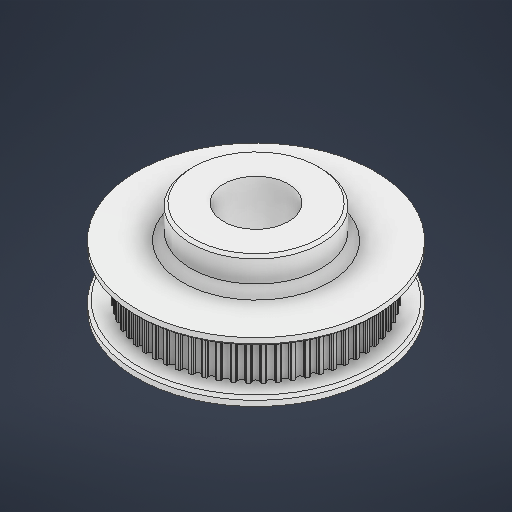
# Autodesk Inventor part: pulleyGT3_12mm
Saved by Autodesk Inventor 2027.1 (Build 311270010, 270A)
## iProperties
Created: 2026-10-09
Part Number: pulleyGT3_12mm
Material: ABS Plastic
Document SubType Name: Modeling
Designer: lucao
Density: 1.06 g/cm^3
Appearance: Smooth - White
Mass: 14.8145 g
Surface Area: 63.8885 cm^2
Volume: 13.9759 cm^3
Author: lucao
Autodesk Inventor part; units mm, degrees
ref_plane "YZ Plane" through (0, 0, 0) normal (1, 0, 0) x (0, 1, 0)
ref_plane "XZ Plane" through (0, 0, 0) normal (0, 1, 0) x (-1, 0, 0)
ref_plane "XY Plane" through (0, 0, 0) normal (0, 0, 1) x (1, 0, 0)
sketch "Sketch1" plane through (0, 0, 0) normal (0, 1, 0) x (-1, 0, 0)
  circle A0 centre (0, 0) radius 19.099
  dimension "d0" = 38.198
  constraints: 1 centre point, 1 coincident
  measures "d0" diameter of A0
extrude "Extrusion1" add sketch "Sketch1" along normal blind 8
sketch "Sketch2" plane through (0, 8, 0) normal (0, 1, 0) x (1, 0, 0)
  circle A0 centre (0, 0) radius 19.099 projected
  line L0 (0, 0) -> (-19.099, 0) construction
  arc A1 (-18.8433, 0.2558) -> (-18.845, 0) centre (0, 0) ccw
  arc A2 (-18.7068, 0.4032) -> (-18.8433, 0.2558) centre (-18.6933, 0.2538) ccw
  arc A3 (-18.7068, 0.4032) -> (-18.4073, 0.4782) centre (-18.7972, 1.3991) ccw
  arc A4 (-18.4073, 0.4782) -> (-18.0695, 0.9599) centre (-18.6237, 0.9893) ccw
  line L1 (0, 0) -> (-18.6237, 0.9893) construction
  arc A5 (-18.8185, 0.9996) -> (-18.8433, 0.2558) centre (0, 0) ccw construction
  arc A6 (-18.5981, 3.0405) -> (-18.8185, 0.9996) centre (0, 0) ccw construction
  arc A7 (-18.7389, 1.9965) -> (-18.7643, 1.7419) centre (0, 0) ccw
  arc A8 (-18.7643, 1.7419) -> (-18.6443, 1.5809) centre (-18.615, 1.728) ccw
  arc A9 (-18.3544, 1.4746) -> (-18.6443, 1.5809) centre (-18.8397, 0.6002) ccw
  arc A10 (-18.0695, 0.9599) -> (-18.3544, 1.4746) centre (-18.6237, 0.9893) ccw
  arc A11 (-18.7668, -1.7152) -> (-18.7418, -1.9698) centre (0, 0) ccw
  arc A12 (-18.6465, -1.5544) -> (-18.3565, -1.4485) centre (-18.8405, -0.5734) ccw
  arc A13 (-18.3565, -1.4485) -> (-18.0709, -0.9342) centre (-18.6251, -0.9628) ccw
  arc A14 (-18.0709, -0.9342) -> (-18.408, -0.4521) centre (-18.6251, -0.9628) ccw
  arc A15 (-18.8436, -0.229) -> (-18.7074, -0.3766) centre (-18.6936, -0.2272) ccw
  arc A16 (-18.408, -0.4521) -> (-18.7074, -0.3766) centre (-18.7992, -1.3724) ccw
  arc A17 (-18.845, 0.0268) -> (-18.8436, -0.229) centre (0, 0) ccw
  arc A18 (-18.6465, -1.5544) -> (-18.7668, -1.7152) centre (-18.6174, -1.7016) ccw
  arc A19 (-18.4847, -3.6675) -> (-18.4332, -3.9181) centre (0, 0) ccw
  arc A20 (-18.3819, -3.495) -> (-18.1045, -3.3593) centre (-18.6774, -2.5397) ccw
  arc A21 (-18.1045, -3.3593) -> (-17.8742, -2.818) centre (-18.4225, -2.9044) ccw
  arc A22 (-17.8742, -2.818) -> (-18.2599, -2.3737) centre (-18.4225, -2.9044) ccw
  arc A23 (-18.7164, -2.1975) -> (-18.5655, -2.33) centre (-18.5675, -2.18) ccw
  arc A24 (-18.2599, -2.3737) -> (-18.5655, -2.33) centre (-18.5528, -3.3299) ccw
  arc A25 (-18.7445, -1.9432) -> (-18.7164, -2.1975) centre (0, 0) ccw
  arc A26 (-18.3819, -3.495) -> (-18.4847, -3.6675) centre (-18.3376, -3.6383) ccw
  arc A27 (-18.0001, -5.5796) -> (-17.9227, -5.8234) centre (0, 0) ccw
  arc A28 (-17.9159, -5.3973) -> (-17.6542, -5.2334) centre (-18.3096, -4.4781) ccw
  arc A29 (-17.6542, -5.2334) -> (-17.4818, -4.6709) centre (-18.0179, -4.8142) ccw
  arc A30 (-17.4818, -4.6709) -> (-17.9118, -4.2694) centre (-18.0179, -4.8142) ccw
  arc A31 (-18.3842, -4.1418) -> (-18.2203, -4.2578) centre (-18.2379, -4.1089) ccw
  arc A32 (-17.9118, -4.2694) -> (-18.2203, -4.2578) centre (-18.1031, -5.2509) ccw
  arc A33 (-18.4387, -3.8919) -> (-18.3842, -4.1418) centre (0, 0) ccw
  arc A34 (-17.9159, -5.3973) -> (-18.0001, -5.5796) centre (-17.8568, -5.5352) ccw
  arc A35 (-17.3182, -7.4305) -> (-17.2158, -7.665) centre (0, 0) ccw
  arc A36 (-17.2535, -7.2404) -> (-17.0105, -7.0501) centre (-17.7412, -6.3674) ccw
  arc A37 (-17.0105, -7.0501) -> (-16.8977, -6.4727) centre (-17.416, -6.6712) ccw
  arc A38 (-16.8977, -6.4727) -> (-17.3674, -6.1183) centre (-17.416, -6.6712) ccw
  arc A39 (-17.8506, -6.0408) -> (-17.6754, -6.1391) centre (-17.7085, -5.9927) ccw
  arc A40 (-17.3674, -6.1183) -> (-17.6754, -6.1391) centre (-17.455, -7.1145) ccw
  arc A41 (-17.9309, -5.7979) -> (-17.8506, -6.0408) centre (0, 0) ccw
  arc A42 (-17.2535, -7.2404) -> (-17.3182, -7.4305) centre (-17.1804, -7.3714) ccw
  arc A43 (-16.4467, -9.2001) -> (-16.3202, -9.4225) centre (0, 0) ccw
  arc A44 (-16.4022, -9.0043) -> (-16.1803, -8.7895) centre (-16.9784, -8.187) ccw
  arc A45 (-16.1803, -8.7895) -> (-16.1286, -8.2035) centre (-16.6233, -8.4551) ccw
  arc A46 (-16.1286, -8.2035) -> (-16.6327, -7.9002) centre (-16.6233, -8.4551) ccw
  arc A47 (-17.1213, -7.8736) -> (-16.9369, -7.953) centre (-16.9851, -7.811) ccw
  arc A48 (-16.6327, -7.9002) -> (-16.9369, -7.953) centre (-16.6158, -8.9) ccw
  arc A49 (-17.2266, -7.6405) -> (-17.1213, -7.8736) centre (0, 0) ccw
  arc A50 (-16.4022, -9.0043) -> (-16.4467, -9.2001) centre (-16.3158, -9.1268) ccw
  arc A51 (-15.3949, -10.8688) -> (-15.2459, -11.0768) centre (0, 0) ccw
  arc A52 (-15.3711, -10.6694) -> (-15.173, -10.4327) centre (-16.0297, -9.9169) ccw
  arc A53 (-15.173, -10.4327) -> (-15.1827, -9.8445) centre (-15.6484, -10.1464) ccw
  arc A54 (-15.1827, -9.8445) -> (-15.7158, -9.5955) centre (-15.6484, -10.1464) ccw
  arc A55 (-16.2045, -9.6202) -> (-16.0128, -9.6798) centre (-16.0755, -9.5436) ccw
  arc A56 (-15.7158, -9.5955) -> (-16.0128, -9.6798) centre (-15.5944, -10.5881) ccw
  arc A57 (-16.3336, -9.3993) -> (-16.2045, -9.6202) centre (0, 0) ccw
  arc A58 (-15.3711, -10.6694) -> (-15.3949, -10.8688) centre (-15.2724, -10.7823) ccw
  arc A59 (-14.1745, -12.4185) -> (-14.0046, -12.6098) centre (0, 0) ccw
  arc A60 (-14.1717, -12.2177) -> (-13.9993, -11.9615) centre (-14.9052, -11.5381) ccw
  arc A61 (-13.9993, -11.9615) -> (-14.0705, -11.3776) centre (-14.5021, -11.7265) ccw
  arc A62 (-14.0705, -11.3776) -> (-14.6267, -11.1857) centre (-14.5021, -11.7265) ccw
  arc A63 (-15.1102, -11.2613) -> (-14.9132, -11.3006) centre (-14.9899, -11.1717) ccw
  arc A64 (-14.6267, -11.1857) -> (-14.9132, -11.3006) centre (-14.4022, -12.1602) ccw
  arc A65 (-15.2617, -11.0551) -> (-15.1102, -11.2613) centre (0, 0) ccw
  arc A66 (-14.1717, -12.2177) -> (-14.1745, -12.4185) centre (-14.0616, -12.3196) ccw
  arc A67 (-12.7987, -13.8321) -> (-12.6098, -14.0046) centre (0, 0) ccw
  arc A68 (-12.8169, -13.6321) -> (-12.6723, -13.3593) centre (-13.6175, -13.0329) ccw
  arc A69 (-12.6723, -13.3593) -> (-12.8042, -12.786) centre (-13.1969, -13.1782) ccw
  arc A70 (-12.8042, -12.786) -> (-13.3773, -12.6533) centre (-13.1969, -13.1782) ccw
  arc A71 (-13.8503, -12.779) -> (-13.6503, -12.7975) centre (-13.74, -12.6773) ccw
  arc A72 (-13.3773, -12.6533) -> (-13.6503, -12.7975) centre (-13.0523, -13.599) ccw
  arc A73 (-14.0225, -12.5898) -> (-13.8503, -12.779) centre (0, 0) ccw
  arc A74 (-12.8169, -13.6321) -> (-12.7987, -13.8321) centre (-12.6969, -13.722) ccw
  arc A75 (-11.2828, -15.0941) -> (-11.0768, -15.2459) centre (0, 0) ccw
  arc A76 (-11.3218, -14.8972) -> (-11.2065, -14.6108) centre (-12.1806, -14.3849) ccw
  arc A77 (-11.2065, -14.6108) -> (-11.3975, -14.0544) centre (-11.7471, -14.4854) ccw
  arc A78 (-11.3975, -14.0544) -> (-11.9814, -13.9823) centre (-11.7471, -14.4854) ccw
  arc A79 (-12.4386, -14.1568) -> (-12.2378, -14.1543) centre (-12.3396, -14.0441) ccw
  arc A80 (-11.9814, -13.9823) -> (-12.2378, -14.1543) centre (-11.5593, -14.8888) ccw
  arc A81 (-12.6297, -13.9866) -> (-12.4386, -14.1568) centre (0, 0) ccw
  arc A82 (-11.3218, -14.8972) -> (-11.2828, -15.0941) centre (-11.193, -14.974) ccw
  arc A83 (-9.6432, -16.1908) -> (-9.4225, -16.3202) centre (0, 0) ccw
  arc A84 (-9.7026, -15.999) -> (-9.6178, -15.7021) centre (-10.6103, -15.5794) ccw
  arc A85 (-9.6178, -15.7021) -> (-9.866, -15.1687) centre (-10.1686, -15.634) ccw
  arc A86 (-9.866, -15.1687) -> (-10.4542, -15.1581) centre (-10.1686, -15.634) ccw
  arc A87 (-10.8907, -15.3794) -> (-10.6913, -15.356) centre (-10.804, -15.257) ccw
  arc A88 (-10.4542, -15.1581) -> (-10.6913, -15.356) centre (-9.9396, -16.0155) ccw
  arc A89 (-11.0985, -15.2302) -> (-10.8907, -15.3794) centre (0, 0) ccw
  arc A90 (-9.7026, -15.999) -> (-9.6432, -16.1908) centre (-9.5664, -16.062) ccw
  arc A91 (-7.898, -17.1101) -> (-7.665, -17.2158) centre (0, 0) ccw
  arc A92 (-7.9771, -16.9256) -> (-7.9238, -16.6214) centre (-8.9237, -16.6031) ccw
  arc A93 (-7.9238, -16.6214) -> (-8.2264, -16.1169) centre (-8.4787, -16.6112) ccw
  arc A94 (-8.2264, -16.1169) -> (-8.8125, -16.1678) centre (-8.4787, -16.6112) ccw
  arc A95 (-9.2234, -16.4336) -> (-9.0276, -16.3894) centre (-9.15, -16.3028) ccw
  arc A96 (-8.8125, -16.1678) -> (-9.0276, -16.3894) centre (-8.2111, -16.9668) ccw
  arc A97 (-9.4457, -16.3068) -> (-9.2234, -16.4336) centre (0, 0) ccw
  arc A98 (-7.9771, -16.9256) -> (-7.898, -17.1101) centre (-7.8351, -16.9739) ccw
  arc A99 (-6.0662, -17.842) -> (-5.8234, -17.9227) centre (0, 0) ccw
  arc A100 (-6.1642, -17.6667) -> (-6.143, -17.3586) centre (-7.1393, -17.4449) ccw
  arc A101 (-6.143, -17.3586) -> (-6.4967, -16.8885) centre (-6.6959, -17.4065) ccw
  arc A102 (-6.4967, -16.8885) -> (-7.0742, -17.0004) centre (-6.6959, -17.4065) ccw
  arc A103 (-7.4551, -17.3077) -> (-7.265, -17.2432) centre (-7.3958, -17.1699) ccw
  arc A104 (-7.0742, -17.0004) -> (-7.265, -17.2432) centre (-6.3926, -17.7321) ccw
  arc A105 (-7.6894, -17.2048) -> (-7.4551, -17.3077) centre (0, 0) ccw
  arc A106 (-6.1642, -17.6667) -> (-6.0662, -17.842) centre (-6.0179, -17.6999) ccw
  arc A107 (-4.168, -18.3783) -> (-3.9181, -18.4332) centre (0, 0) ccw
  arc A108 (-4.2837, -18.2142) -> (-4.2949, -17.9057) centre (-5.2767, -18.0956) ccw
  arc A109 (-4.2949, -17.9057) -> (-4.6958, -17.4751) centre (-4.8398, -18.0111) ccw
  arc A110 (-4.6958, -17.4751) -> (-5.2585, -17.6467) centre (-4.8398, -18.0111) ccw
  arc A111 (-5.6052, -17.9921) -> (-5.4227, -17.9082) centre (-5.5605, -17.8489) ccw
  arc A112 (-5.2585, -17.6467) -> (-5.4227, -17.9082) centre (-4.5041, -18.3032) ccw
  arc A113 (-5.8489, -17.9144) -> (-5.6052, -17.9921) centre (0, 0) ccw
  arc A114 (-4.2837, -18.2142) -> (-4.168, -18.3783) centre (-4.1348, -18.232) ccw
  arc A115 (-2.2241, -18.7133) -> (-1.9698, -18.7418) centre (0, 0) ccw
  arc A116 (-2.3564, -18.5622) -> (-2.3997, -18.2565) centre (-3.3563, -18.548) ccw
  arc A117 (-2.3997, -18.2565) -> (-2.8434, -17.8702) centre (-2.9306, -18.4183) ccw
  arc A118 (-2.8434, -17.8702) -> (-3.3851, -18.0997) centre (-2.9306, -18.4183) ccw
  arc A119 (-3.6938, -18.4795) -> (-3.5211, -18.3769) centre (-3.6644, -18.3324) ccw
  arc A120 (-3.3851, -18.0997) -> (-3.5211, -18.3769) centre (-2.5662, -18.6737) ccw
  arc A121 (-3.9443, -18.4276) -> (-3.6938, -18.4795) centre (0, 0) ccw
  arc A122 (-2.3564, -18.5622) -> (-2.2241, -18.7133) centre (-2.2064, -18.5643) ccw
  arc A123 (-0.2558, -18.8433) -> (0, -18.845) centre (0, 0) ccw
  arc A124 (-0.4032, -18.7068) -> (-0.4782, -18.4073) centre (-1.3991, -18.7972) ccw
  arc A125 (-0.4782, -18.4073) -> (-0.9599, -18.0695) centre (-0.9893, -18.6237) ccw
  arc A126 (-0.9599, -18.0695) -> (-1.4746, -18.3544) centre (-0.9893, -18.6237) ccw
  arc A127 (-1.7419, -18.7643) -> (-1.5809, -18.6443) centre (-1.728, -18.615) ccw
  arc A128 (-1.4746, -18.3544) -> (-1.5809, -18.6443) centre (-0.6002, -18.8397) ccw
  arc A129 (-1.9965, -18.7389) -> (-1.7419, -18.7643) centre (0, 0) ccw
  arc A130 (-0.4032, -18.7068) -> (-0.2558, -18.8433) centre (-0.2538, -18.6933) ccw
  arc A131 (1.7152, -18.7668) -> (1.9698, -18.7418) centre (0, 0) ccw
  arc A132 (1.5544, -18.6465) -> (1.4485, -18.3565) centre (0.5734, -18.8405) ccw
  arc A133 (1.4485, -18.3565) -> (0.9342, -18.0709) centre (0.9628, -18.6251) ccw
  arc A134 (0.9342, -18.0709) -> (0.4521, -18.408) centre (0.9628, -18.6251) ccw
  arc A135 (0.229, -18.8436) -> (0.3766, -18.7074) centre (0.2272, -18.6936) ccw
  arc A136 (0.4521, -18.408) -> (0.3766, -18.7074) centre (1.3724, -18.7992) ccw
  arc A137 (-0.0268, -18.845) -> (0.229, -18.8436) centre (0, 0) ccw
  arc A138 (1.5544, -18.6465) -> (1.7152, -18.7668) centre (1.7016, -18.6174) ccw
  arc A139 (3.6675, -18.4847) -> (3.9181, -18.4332) centre (0, 0) ccw
  arc A140 (3.495, -18.3819) -> (3.3593, -18.1045) centre (2.5397, -18.6774) ccw
  arc A141 (3.3593, -18.1045) -> (2.818, -17.8742) centre (2.9044, -18.4225) ccw
  arc A142 (2.818, -17.8742) -> (2.3737, -18.2599) centre (2.9044, -18.4225) ccw
  arc A143 (2.1975, -18.7164) -> (2.33, -18.5655) centre (2.18, -18.5675) ccw
  arc A144 (2.3737, -18.2599) -> (2.33, -18.5655) centre (3.3299, -18.5528) ccw
  arc A145 (1.9432, -18.7445) -> (2.1975, -18.7164) centre (0, 0) ccw
  arc A146 (3.495, -18.3819) -> (3.6675, -18.4847) centre (3.6383, -18.3376) ccw
  arc A147 (5.5796, -18.0001) -> (5.8234, -17.9227) centre (0, 0) ccw
  arc A148 (5.3973, -17.9159) -> (5.2334, -17.6542) centre (4.4781, -18.3096) ccw
  arc A149 (5.2334, -17.6542) -> (4.6709, -17.4818) centre (4.8142, -18.0179) ccw
  arc A150 (4.6709, -17.4818) -> (4.2694, -17.9118) centre (4.8142, -18.0179) ccw
  arc A151 (4.1418, -18.3842) -> (4.2578, -18.2203) centre (4.1089, -18.2379) ccw
  arc A152 (4.2694, -17.9118) -> (4.2578, -18.2203) centre (5.2509, -18.1031) ccw
  arc A153 (3.8919, -18.4387) -> (4.1418, -18.3842) centre (0, 0) ccw
  arc A154 (5.3973, -17.9159) -> (5.5796, -18.0001) centre (5.5352, -17.8568) ccw
  arc A155 (7.4305, -17.3182) -> (7.665, -17.2158) centre (0, 0) ccw
  arc A156 (7.2404, -17.2535) -> (7.0501, -17.0105) centre (6.3674, -17.7412) ccw
  arc A157 (7.0501, -17.0105) -> (6.4727, -16.8977) centre (6.6712, -17.416) ccw
  arc A158 (6.4727, -16.8977) -> (6.1183, -17.3674) centre (6.6712, -17.416) ccw
  arc A159 (6.0408, -17.8506) -> (6.1391, -17.6754) centre (5.9927, -17.7085) ccw
  arc A160 (6.1183, -17.3674) -> (6.1391, -17.6754) centre (7.1145, -17.455) ccw
  arc A161 (5.7979, -17.9309) -> (6.0408, -17.8506) centre (0, 0) ccw
  arc A162 (7.2404, -17.2535) -> (7.4305, -17.3182) centre (7.3714, -17.1804) ccw
  arc A163 (9.2001, -16.4467) -> (9.4225, -16.3202) centre (0, 0) ccw
  arc A164 (9.0043, -16.4022) -> (8.7895, -16.1803) centre (8.187, -16.9784) ccw
  arc A165 (8.7895, -16.1803) -> (8.2035, -16.1286) centre (8.4551, -16.6233) ccw
  arc A166 (8.2035, -16.1286) -> (7.9002, -16.6327) centre (8.4551, -16.6233) ccw
  arc A167 (7.8736, -17.1213) -> (7.953, -16.9369) centre (7.811, -16.9851) ccw
  arc A168 (7.9002, -16.6327) -> (7.953, -16.9369) centre (8.9, -16.6158) ccw
  arc A169 (7.6405, -17.2266) -> (7.8736, -17.1213) centre (0, 0) ccw
  arc A170 (9.0043, -16.4022) -> (9.2001, -16.4467) centre (9.1268, -16.3158) ccw
  arc A171 (10.8688, -15.3949) -> (11.0768, -15.2459) centre (0, 0) ccw
  arc A172 (10.6694, -15.3711) -> (10.4327, -15.173) centre (9.9169, -16.0297) ccw
  arc A173 (10.4327, -15.173) -> (9.8445, -15.1827) centre (10.1464, -15.6484) ccw
  arc A174 (9.8445, -15.1827) -> (9.5955, -15.7158) centre (10.1464, -15.6484) ccw
  arc A175 (9.6202, -16.2045) -> (9.6798, -16.0128) centre (9.5436, -16.0755) ccw
  arc A176 (9.5955, -15.7158) -> (9.6798, -16.0128) centre (10.5881, -15.5944) ccw
  arc A177 (9.3993, -16.3336) -> (9.6202, -16.2045) centre (0, 0) ccw
  arc A178 (10.6694, -15.3711) -> (10.8688, -15.3949) centre (10.7823, -15.2724) ccw
  arc A179 (12.4185, -14.1745) -> (12.6098, -14.0046) centre (0, 0) ccw
  arc A180 (12.2177, -14.1717) -> (11.9615, -13.9993) centre (11.5381, -14.9052) ccw
  arc A181 (11.9615, -13.9993) -> (11.3776, -14.0705) centre (11.7265, -14.5021) ccw
  arc A182 (11.3776, -14.0705) -> (11.1857, -14.6267) centre (11.7265, -14.5021) ccw
  arc A183 (11.2613, -15.1102) -> (11.3006, -14.9132) centre (11.1717, -14.9899) ccw
  arc A184 (11.1857, -14.6267) -> (11.3006, -14.9132) centre (12.1602, -14.4022) ccw
  arc A185 (11.0551, -15.2617) -> (11.2613, -15.1102) centre (0, 0) ccw
  arc A186 (12.2177, -14.1717) -> (12.4185, -14.1745) centre (12.3196, -14.0616) ccw
  arc A187 (13.8321, -12.7987) -> (14.0046, -12.6098) centre (0, 0) ccw
  arc A188 (13.6321, -12.8169) -> (13.3593, -12.6723) centre (13.0329, -13.6175) ccw
  arc A189 (13.3593, -12.6723) -> (12.786, -12.8042) centre (13.1782, -13.1969) ccw
  arc A190 (12.786, -12.8042) -> (12.6533, -13.3773) centre (13.1782, -13.1969) ccw
  arc A191 (12.779, -13.8503) -> (12.7975, -13.6503) centre (12.6773, -13.74) ccw
  arc A192 (12.6533, -13.3773) -> (12.7975, -13.6503) centre (13.599, -13.0523) ccw
  arc A193 (12.5898, -14.0225) -> (12.779, -13.8503) centre (0, 0) ccw
  arc A194 (13.6321, -12.8169) -> (13.8321, -12.7987) centre (13.722, -12.6969) ccw
  arc A195 (15.0941, -11.2828) -> (15.2459, -11.0768) centre (0, 0) ccw
  arc A196 (14.8972, -11.3218) -> (14.6108, -11.2065) centre (14.3849, -12.1806) ccw
  arc A197 (14.6108, -11.2065) -> (14.0544, -11.3975) centre (14.4854, -11.7471) ccw
  arc A198 (14.0544, -11.3975) -> (13.9823, -11.9814) centre (14.4854, -11.7471) ccw
  arc A199 (14.1568, -12.4386) -> (14.1543, -12.2378) centre (14.0441, -12.3396) ccw
  arc A200 (13.9823, -11.9814) -> (14.1543, -12.2378) centre (14.8888, -11.5593) ccw
  arc A201 (13.9866, -12.6297) -> (14.1568, -12.4386) centre (0, 0) ccw
  arc A202 (14.8972, -11.3218) -> (15.0941, -11.2828) centre (14.974, -11.193) ccw
  arc A203 (16.1908, -9.6432) -> (16.3202, -9.4225) centre (0, 0) ccw
  arc A204 (15.999, -9.7026) -> (15.7021, -9.6178) centre (15.5794, -10.6103) ccw
  arc A205 (15.7021, -9.6178) -> (15.1687, -9.866) centre (15.634, -10.1686) ccw
  arc A206 (15.1687, -9.866) -> (15.1581, -10.4542) centre (15.634, -10.1686) ccw
  arc A207 (15.3794, -10.8907) -> (15.356, -10.6913) centre (15.257, -10.804) ccw
  arc A208 (15.1581, -10.4542) -> (15.356, -10.6913) centre (16.0155, -9.9396) ccw
  arc A209 (15.2302, -11.0985) -> (15.3794, -10.8907) centre (0, 0) ccw
  arc A210 (15.999, -9.7026) -> (16.1908, -9.6432) centre (16.062, -9.5664) ccw
  arc A211 (17.1101, -7.898) -> (17.2158, -7.665) centre (0, 0) ccw
  arc A212 (16.9256, -7.9771) -> (16.6214, -7.9238) centre (16.6031, -8.9237) ccw
  arc A213 (16.6214, -7.9238) -> (16.1169, -8.2264) centre (16.6112, -8.4787) ccw
  arc A214 (16.1169, -8.2264) -> (16.1678, -8.8125) centre (16.6112, -8.4787) ccw
  arc A215 (16.4336, -9.2234) -> (16.3894, -9.0276) centre (16.3028, -9.15) ccw
  arc A216 (16.1678, -8.8125) -> (16.3894, -9.0276) centre (16.9668, -8.2111) ccw
  arc A217 (16.3068, -9.4457) -> (16.4336, -9.2234) centre (0, 0) ccw
  arc A218 (16.9256, -7.9771) -> (17.1101, -7.898) centre (16.9739, -7.8351) ccw
  arc A219 (17.842, -6.0662) -> (17.9227, -5.8234) centre (0, 0) ccw
  arc A220 (17.6667, -6.1642) -> (17.3586, -6.143) centre (17.4449, -7.1393) ccw
  arc A221 (17.3586, -6.143) -> (16.8885, -6.4967) centre (17.4065, -6.6959) ccw
  arc A222 (16.8885, -6.4967) -> (17.0004, -7.0742) centre (17.4065, -6.6959) ccw
  arc A223 (17.3077, -7.4551) -> (17.2432, -7.265) centre (17.1699, -7.3958) ccw
  arc A224 (17.0004, -7.0742) -> (17.2432, -7.265) centre (17.7321, -6.3926) ccw
  arc A225 (17.2048, -7.6894) -> (17.3077, -7.4551) centre (0, 0) ccw
  arc A226 (17.6667, -6.1642) -> (17.842, -6.0662) centre (17.6999, -6.0179) ccw
  arc A227 (18.3783, -4.168) -> (18.4332, -3.9181) centre (0, 0) ccw
  arc A228 (18.2142, -4.2837) -> (17.9057, -4.2949) centre (18.0956, -5.2767) ccw
  arc A229 (17.9057, -4.2949) -> (17.4751, -4.6958) centre (18.0111, -4.8398) ccw
  arc A230 (17.4751, -4.6958) -> (17.6467, -5.2585) centre (18.0111, -4.8398) ccw
  arc A231 (17.9921, -5.6052) -> (17.9082, -5.4227) centre (17.8489, -5.5605) ccw
  arc A232 (17.6467, -5.2585) -> (17.9082, -5.4227) centre (18.3032, -4.5041) ccw
  arc A233 (17.9144, -5.8489) -> (17.9921, -5.6052) centre (0, 0) ccw
  arc A234 (18.2142, -4.2837) -> (18.3783, -4.168) centre (18.232, -4.1348) ccw
  arc A235 (18.7133, -2.2241) -> (18.7418, -1.9698) centre (0, 0) ccw
  arc A236 (18.5622, -2.3564) -> (18.2565, -2.3997) centre (18.548, -3.3563) ccw
  arc A237 (18.2565, -2.3997) -> (17.8702, -2.8434) centre (18.4183, -2.9306) ccw
  arc A238 (17.8702, -2.8434) -> (18.0997, -3.3851) centre (18.4183, -2.9306) ccw
  arc A239 (18.4795, -3.6938) -> (18.3769, -3.5211) centre (18.3324, -3.6644) ccw
  arc A240 (18.0997, -3.3851) -> (18.3769, -3.5211) centre (18.6737, -2.5662) ccw
  arc A241 (18.4276, -3.9443) -> (18.4795, -3.6938) centre (0, 0) ccw
  arc A242 (18.5622, -2.3564) -> (18.7133, -2.2241) centre (18.5643, -2.2064) ccw
  arc A243 (18.8433, -0.2558) -> (18.845, 0) centre (0, 0) ccw
  arc A244 (18.7068, -0.4032) -> (18.4073, -0.4782) centre (18.7972, -1.3991) ccw
  arc A245 (18.4073, -0.4782) -> (18.0695, -0.9599) centre (18.6237, -0.9893) ccw
  arc A246 (18.0695, -0.9599) -> (18.3544, -1.4746) centre (18.6237, -0.9893) ccw
  arc A247 (18.7643, -1.7419) -> (18.6443, -1.5809) centre (18.615, -1.728) ccw
  arc A248 (18.3544, -1.4746) -> (18.6443, -1.5809) centre (18.8397, -0.6002) ccw
  arc A249 (18.7389, -1.9965) -> (18.7643, -1.7419) centre (0, 0) ccw
  arc A250 (18.7068, -0.4032) -> (18.8433, -0.2558) centre (18.6933, -0.2538) ccw
  arc A251 (18.7668, 1.7152) -> (18.7418, 1.9698) centre (0, 0) ccw
  arc A252 (18.6465, 1.5544) -> (18.3565, 1.4485) centre (18.8405, 0.5734) ccw
  arc A253 (18.3565, 1.4485) -> (18.0709, 0.9342) centre (18.6251, 0.9628) ccw
  arc A254 (18.0709, 0.9342) -> (18.408, 0.4521) centre (18.6251, 0.9628) ccw
  arc A255 (18.8436, 0.229) -> (18.7074, 0.3766) centre (18.6936, 0.2272) ccw
  arc A256 (18.408, 0.4521) -> (18.7074, 0.3766) centre (18.7992, 1.3724) ccw
  arc A257 (18.845, -0.0268) -> (18.8436, 0.229) centre (0, 0) ccw
  arc A258 (18.6465, 1.5544) -> (18.7668, 1.7152) centre (18.6174, 1.7016) ccw
  arc A259 (18.4847, 3.6675) -> (18.4332, 3.9181) centre (0, 0) ccw
  arc A260 (18.3819, 3.495) -> (18.1045, 3.3593) centre (18.6774, 2.5397) ccw
  arc A261 (18.1045, 3.3593) -> (17.8742, 2.818) centre (18.4225, 2.9044) ccw
  arc A262 (17.8742, 2.818) -> (18.2599, 2.3737) centre (18.4225, 2.9044) ccw
  arc A263 (18.7164, 2.1975) -> (18.5655, 2.33) centre (18.5675, 2.18) ccw
  arc A264 (18.2599, 2.3737) -> (18.5655, 2.33) centre (18.5528, 3.3299) ccw
  arc A265 (18.7445, 1.9432) -> (18.7164, 2.1975) centre (0, 0) ccw
  arc A266 (18.3819, 3.495) -> (18.4847, 3.6675) centre (18.3376, 3.6383) ccw
  arc A267 (18.0001, 5.5796) -> (17.9227, 5.8234) centre (0, 0) ccw
  arc A268 (17.9159, 5.3973) -> (17.6542, 5.2334) centre (18.3096, 4.4781) ccw
  arc A269 (17.6542, 5.2334) -> (17.4818, 4.6709) centre (18.0179, 4.8142) ccw
  arc A270 (17.4818, 4.6709) -> (17.9118, 4.2694) centre (18.0179, 4.8142) ccw
  arc A271 (18.3842, 4.1418) -> (18.2203, 4.2578) centre (18.2379, 4.1089) ccw
  arc A272 (17.9118, 4.2694) -> (18.2203, 4.2578) centre (18.1031, 5.2509) ccw
  arc A273 (18.4387, 3.8919) -> (18.3842, 4.1418) centre (0, 0) ccw
  arc A274 (17.9159, 5.3973) -> (18.0001, 5.5796) centre (17.8568, 5.5352) ccw
  arc A275 (17.3182, 7.4305) -> (17.2158, 7.665) centre (0, 0) ccw
  arc A276 (17.2535, 7.2404) -> (17.0105, 7.0501) centre (17.7412, 6.3674) ccw
  arc A277 (17.0105, 7.0501) -> (16.8977, 6.4727) centre (17.416, 6.6712) ccw
  arc A278 (16.8977, 6.4727) -> (17.3674, 6.1183) centre (17.416, 6.6712) ccw
  arc A279 (17.8506, 6.0408) -> (17.6754, 6.1391) centre (17.7085, 5.9927) ccw
  arc A280 (17.3674, 6.1183) -> (17.6754, 6.1391) centre (17.455, 7.1145) ccw
  arc A281 (17.9309, 5.7979) -> (17.8506, 6.0408) centre (0, 0) ccw
  arc A282 (17.2535, 7.2404) -> (17.3182, 7.4305) centre (17.1804, 7.3714) ccw
  arc A283 (16.4467, 9.2001) -> (16.3202, 9.4225) centre (0, 0) ccw
  arc A284 (16.4022, 9.0043) -> (16.1803, 8.7895) centre (16.9784, 8.187) ccw
  arc A285 (16.1803, 8.7895) -> (16.1286, 8.2035) centre (16.6233, 8.4551) ccw
  arc A286 (16.1286, 8.2035) -> (16.6327, 7.9002) centre (16.6233, 8.4551) ccw
  arc A287 (17.1213, 7.8736) -> (16.9369, 7.953) centre (16.9851, 7.811) ccw
  arc A288 (16.6327, 7.9002) -> (16.9369, 7.953) centre (16.6158, 8.9) ccw
  arc A289 (17.2266, 7.6405) -> (17.1213, 7.8736) centre (0, 0) ccw
  arc A290 (16.4022, 9.0043) -> (16.4467, 9.2001) centre (16.3158, 9.1268) ccw
  arc A291 (15.3949, 10.8688) -> (15.2459, 11.0768) centre (0, 0) ccw
  arc A292 (15.3711, 10.6694) -> (15.173, 10.4327) centre (16.0297, 9.9169) ccw
  arc A293 (15.173, 10.4327) -> (15.1827, 9.8445) centre (15.6484, 10.1464) ccw
  arc A294 (15.1827, 9.8445) -> (15.7158, 9.5955) centre (15.6484, 10.1464) ccw
  arc A295 (16.2045, 9.6202) -> (16.0128, 9.6798) centre (16.0755, 9.5436) ccw
  arc A296 (15.7158, 9.5955) -> (16.0128, 9.6798) centre (15.5944, 10.5881) ccw
  arc A297 (16.3336, 9.3993) -> (16.2045, 9.6202) centre (0, 0) ccw
  arc A298 (15.3711, 10.6694) -> (15.3949, 10.8688) centre (15.2724, 10.7823) ccw
  arc A299 (14.1745, 12.4185) -> (14.0046, 12.6098) centre (0, 0) ccw
  arc A300 (14.1717, 12.2177) -> (13.9993, 11.9615) centre (14.9052, 11.5381) ccw
  arc A301 (13.9993, 11.9615) -> (14.0705, 11.3776) centre (14.5021, 11.7265) ccw
  arc A302 (14.0705, 11.3776) -> (14.6267, 11.1857) centre (14.5021, 11.7265) ccw
  arc A303 (15.1102, 11.2613) -> (14.9132, 11.3006) centre (14.9899, 11.1717) ccw
  arc A304 (14.6267, 11.1857) -> (14.9132, 11.3006) centre (14.4022, 12.1602) ccw
  arc A305 (15.2617, 11.0551) -> (15.1102, 11.2613) centre (0, 0) ccw
  arc A306 (14.1717, 12.2177) -> (14.1745, 12.4185) centre (14.0616, 12.3196) ccw
  arc A307 (12.7987, 13.8321) -> (12.6098, 14.0046) centre (0, 0) ccw
  arc A308 (12.8169, 13.6321) -> (12.6723, 13.3593) centre (13.6175, 13.0329) ccw
  arc A309 (12.6723, 13.3593) -> (12.8042, 12.786) centre (13.1969, 13.1782) ccw
  arc A310 (12.8042, 12.786) -> (13.3773, 12.6533) centre (13.1969, 13.1782) ccw
  arc A311 (13.8503, 12.779) -> (13.6503, 12.7975) centre (13.74, 12.6773) ccw
  arc A312 (13.3773, 12.6533) -> (13.6503, 12.7975) centre (13.0523, 13.599) ccw
  arc A313 (14.0225, 12.5898) -> (13.8503, 12.779) centre (0, 0) ccw
  arc A314 (12.8169, 13.6321) -> (12.7987, 13.8321) centre (12.6969, 13.722) ccw
  arc A315 (11.2828, 15.0941) -> (11.0768, 15.2459) centre (0, 0) ccw
  arc A316 (11.3218, 14.8972) -> (11.2065, 14.6108) centre (12.1806, 14.3849) ccw
  arc A317 (11.2065, 14.6108) -> (11.3975, 14.0544) centre (11.7471, 14.4854) ccw
  arc A318 (11.3975, 14.0544) -> (11.9814, 13.9823) centre (11.7471, 14.4854) ccw
  arc A319 (12.4386, 14.1568) -> (12.2378, 14.1543) centre (12.3396, 14.0441) ccw
  arc A320 (11.9814, 13.9823) -> (12.2378, 14.1543) centre (11.5593, 14.8888) ccw
  arc A321 (12.6297, 13.9866) -> (12.4386, 14.1568) centre (0, 0) ccw
  arc A322 (11.3218, 14.8972) -> (11.2828, 15.0941) centre (11.193, 14.974) ccw
  arc A323 (9.6432, 16.1908) -> (9.4225, 16.3202) centre (0, 0) ccw
  arc A324 (9.7026, 15.999) -> (9.6178, 15.7021) centre (10.6103, 15.5794) ccw
  arc A325 (9.6178, 15.7021) -> (9.866, 15.1687) centre (10.1686, 15.634) ccw
  arc A326 (9.866, 15.1687) -> (10.4542, 15.1581) centre (10.1686, 15.634) ccw
  arc A327 (10.8907, 15.3794) -> (10.6913, 15.356) centre (10.804, 15.257) ccw
  arc A328 (10.4542, 15.1581) -> (10.6913, 15.356) centre (9.9396, 16.0155) ccw
  arc A329 (11.0985, 15.2302) -> (10.8907, 15.3794) centre (0, 0) ccw
  arc A330 (9.7026, 15.999) -> (9.6432, 16.1908) centre (9.5664, 16.062) ccw
  arc A331 (7.898, 17.1101) -> (7.665, 17.2158) centre (0, 0) ccw
  arc A332 (7.9771, 16.9256) -> (7.9238, 16.6214) centre (8.9237, 16.6031) ccw
  arc A333 (7.9238, 16.6214) -> (8.2264, 16.1169) centre (8.4787, 16.6112) ccw
  arc A334 (8.2264, 16.1169) -> (8.8125, 16.1678) centre (8.4787, 16.6112) ccw
  arc A335 (9.2234, 16.4336) -> (9.0276, 16.3894) centre (9.15, 16.3028) ccw
  arc A336 (8.8125, 16.1678) -> (9.0276, 16.3894) centre (8.2111, 16.9668) ccw
  arc A337 (9.4457, 16.3068) -> (9.2234, 16.4336) centre (0, 0) ccw
  arc A338 (7.9771, 16.9256) -> (7.898, 17.1101) centre (7.8351, 16.9739) ccw
  arc A339 (6.0662, 17.842) -> (5.8234, 17.9227) centre (0, 0) ccw
  arc A340 (6.1642, 17.6667) -> (6.143, 17.3586) centre (7.1393, 17.4449) ccw
  arc A341 (6.143, 17.3586) -> (6.4967, 16.8885) centre (6.6959, 17.4065) ccw
  arc A342 (6.4967, 16.8885) -> (7.0742, 17.0004) centre (6.6959, 17.4065) ccw
  arc A343 (7.4551, 17.3077) -> (7.265, 17.2432) centre (7.3958, 17.1699) ccw
  arc A344 (7.0742, 17.0004) -> (7.265, 17.2432) centre (6.3926, 17.7321) ccw
  arc A345 (7.6894, 17.2048) -> (7.4551, 17.3077) centre (0, 0) ccw
  arc A346 (6.1642, 17.6667) -> (6.0662, 17.842) centre (6.0179, 17.6999) ccw
  arc A347 (4.168, 18.3783) -> (3.9181, 18.4332) centre (0, 0) ccw
  arc A348 (4.2837, 18.2142) -> (4.2949, 17.9057) centre (5.2767, 18.0956) ccw
  arc A349 (4.2949, 17.9057) -> (4.6958, 17.4751) centre (4.8398, 18.0111) ccw
  arc A350 (4.6958, 17.4751) -> (5.2585, 17.6467) centre (4.8398, 18.0111) ccw
  arc A351 (5.6052, 17.9921) -> (5.4227, 17.9082) centre (5.5605, 17.8489) ccw
  arc A352 (5.2585, 17.6467) -> (5.4227, 17.9082) centre (4.5041, 18.3032) ccw
  arc A353 (5.8489, 17.9144) -> (5.6052, 17.9921) centre (0, 0) ccw
  arc A354 (4.2837, 18.2142) -> (4.168, 18.3783) centre (4.1348, 18.232) ccw
  arc A355 (2.2241, 18.7133) -> (1.9698, 18.7418) centre (0, 0) ccw
  arc A356 (2.3564, 18.5622) -> (2.3997, 18.2565) centre (3.3563, 18.548) ccw
  arc A357 (2.3997, 18.2565) -> (2.8434, 17.8702) centre (2.9306, 18.4183) ccw
  arc A358 (2.8434, 17.8702) -> (3.3851, 18.0997) centre (2.9306, 18.4183) ccw
  arc A359 (3.6938, 18.4795) -> (3.5211, 18.3769) centre (3.6644, 18.3324) ccw
  arc A360 (3.3851, 18.0997) -> (3.5211, 18.3769) centre (2.5662, 18.6737) ccw
  arc A361 (3.9443, 18.4276) -> (3.6938, 18.4795) centre (0, 0) ccw
  arc A362 (2.3564, 18.5622) -> (2.2241, 18.7133) centre (2.2064, 18.5643) ccw
  arc A363 (0.2558, 18.8433) -> (0, 18.845) centre (0, 0) ccw
  arc A364 (0.4032, 18.7068) -> (0.4782, 18.4073) centre (1.3991, 18.7972) ccw
  arc A365 (0.4782, 18.4073) -> (0.9599, 18.0695) centre (0.9893, 18.6237) ccw
  arc A366 (0.9599, 18.0695) -> (1.4746, 18.3544) centre (0.9893, 18.6237) ccw
  arc A367 (1.7419, 18.7643) -> (1.5809, 18.6443) centre (1.728, 18.615) ccw
  arc A368 (1.4746, 18.3544) -> (1.5809, 18.6443) centre (0.6002, 18.8397) ccw
  arc A369 (1.9965, 18.7389) -> (1.7419, 18.7643) centre (0, 0) ccw
  arc A370 (0.4032, 18.7068) -> (0.2558, 18.8433) centre (0.2538, 18.6933) ccw
  arc A371 (-1.7152, 18.7668) -> (-1.9698, 18.7418) centre (0, 0) ccw
  arc A372 (-1.5544, 18.6465) -> (-1.4485, 18.3565) centre (-0.5734, 18.8405) ccw
  arc A373 (-1.4485, 18.3565) -> (-0.9342, 18.0709) centre (-0.9628, 18.6251) ccw
  arc A374 (-0.9342, 18.0709) -> (-0.4521, 18.408) centre (-0.9628, 18.6251) ccw
  arc A375 (-0.229, 18.8436) -> (-0.3766, 18.7074) centre (-0.2272, 18.6936) ccw
  arc A376 (-0.4521, 18.408) -> (-0.3766, 18.7074) centre (-1.3724, 18.7992) ccw
  arc A377 (0.0268, 18.845) -> (-0.229, 18.8436) centre (0, 0) ccw
  arc A378 (-1.5544, 18.6465) -> (-1.7152, 18.7668) centre (-1.7016, 18.6174) ccw
  arc A379 (-3.6675, 18.4847) -> (-3.9181, 18.4332) centre (0, 0) ccw
  arc A380 (-3.495, 18.3819) -> (-3.3593, 18.1045) centre (-2.5397, 18.6774) ccw
  arc A381 (-3.3593, 18.1045) -> (-2.818, 17.8742) centre (-2.9044, 18.4225) ccw
  arc A382 (-2.818, 17.8742) -> (-2.3737, 18.2599) centre (-2.9044, 18.4225) ccw
  arc A383 (-2.1975, 18.7164) -> (-2.33, 18.5655) centre (-2.18, 18.5675) ccw
  arc A384 (-2.3737, 18.2599) -> (-2.33, 18.5655) centre (-3.3299, 18.5528) ccw
  arc A385 (-1.9432, 18.7445) -> (-2.1975, 18.7164) centre (0, 0) ccw
  arc A386 (-3.495, 18.3819) -> (-3.6675, 18.4847) centre (-3.6383, 18.3376) ccw
  arc A387 (-5.5796, 18.0001) -> (-5.8234, 17.9227) centre (0, 0) ccw
  arc A388 (-5.3973, 17.9159) -> (-5.2334, 17.6542) centre (-4.4781, 18.3096) ccw
  arc A389 (-5.2334, 17.6542) -> (-4.6709, 17.4818) centre (-4.8142, 18.0179) ccw
  arc A390 (-4.6709, 17.4818) -> (-4.2694, 17.9118) centre (-4.8142, 18.0179) ccw
  arc A391 (-4.1418, 18.3842) -> (-4.2578, 18.2203) centre (-4.1089, 18.2379) ccw
  arc A392 (-4.2694, 17.9118) -> (-4.2578, 18.2203) centre (-5.2509, 18.1031) ccw
  arc A393 (-3.8919, 18.4387) -> (-4.1418, 18.3842) centre (0, 0) ccw
  arc A394 (-5.3973, 17.9159) -> (-5.5796, 18.0001) centre (-5.5352, 17.8568) ccw
  arc A395 (-7.4305, 17.3182) -> (-7.665, 17.2158) centre (0, 0) ccw
  arc A396 (-7.2404, 17.2535) -> (-7.0501, 17.0105) centre (-6.3674, 17.7412) ccw
  arc A397 (-7.0501, 17.0105) -> (-6.4727, 16.8977) centre (-6.6712, 17.416) ccw
  arc A398 (-6.4727, 16.8977) -> (-6.1183, 17.3674) centre (-6.6712, 17.416) ccw
  arc A399 (-6.0408, 17.8506) -> (-6.1391, 17.6754) centre (-5.9927, 17.7085) ccw
  arc A400 (-6.1183, 17.3674) -> (-6.1391, 17.6754) centre (-7.1145, 17.455) ccw
  arc A401 (-5.7979, 17.9309) -> (-6.0408, 17.8506) centre (0, 0) ccw
  arc A402 (-7.2404, 17.2535) -> (-7.4305, 17.3182) centre (-7.3714, 17.1804) ccw
  arc A403 (-9.2001, 16.4467) -> (-9.4225, 16.3202) centre (0, 0) ccw
  arc A404 (-9.0043, 16.4022) -> (-8.7895, 16.1803) centre (-8.187, 16.9784) ccw
  arc A405 (-8.7895, 16.1803) -> (-8.2035, 16.1286) centre (-8.4551, 16.6233) ccw
  arc A406 (-8.2035, 16.1286) -> (-7.9002, 16.6327) centre (-8.4551, 16.6233) ccw
  arc A407 (-7.8736, 17.1213) -> (-7.953, 16.9369) centre (-7.811, 16.9851) ccw
  arc A408 (-7.9002, 16.6327) -> (-7.953, 16.9369) centre (-8.9, 16.6158) ccw
  arc A409 (-7.6405, 17.2266) -> (-7.8736, 17.1213) centre (0, 0) ccw
  arc A410 (-9.0043, 16.4022) -> (-9.2001, 16.4467) centre (-9.1268, 16.3158) ccw
  arc A411 (-10.8688, 15.3949) -> (-11.0768, 15.2459) centre (0, 0) ccw
  arc A412 (-10.6694, 15.3711) -> (-10.4327, 15.173) centre (-9.9169, 16.0297) ccw
  arc A413 (-10.4327, 15.173) -> (-9.8445, 15.1827) centre (-10.1464, 15.6484) ccw
  arc A414 (-9.8445, 15.1827) -> (-9.5955, 15.7158) centre (-10.1464, 15.6484) ccw
  arc A415 (-9.6202, 16.2045) -> (-9.6798, 16.0128) centre (-9.5436, 16.0755) ccw
  arc A416 (-9.5955, 15.7158) -> (-9.6798, 16.0128) centre (-10.5881, 15.5944) ccw
  arc A417 (-9.3993, 16.3336) -> (-9.6202, 16.2045) centre (0, 0) ccw
  arc A418 (-10.6694, 15.3711) -> (-10.8688, 15.3949) centre (-10.7823, 15.2724) ccw
  arc A419 (-12.4185, 14.1745) -> (-12.6098, 14.0046) centre (0, 0) ccw
  arc A420 (-12.2177, 14.1717) -> (-11.9615, 13.9993) centre (-11.5381, 14.9052) ccw
  arc A421 (-11.9615, 13.9993) -> (-11.3776, 14.0705) centre (-11.7265, 14.5021) ccw
  arc A422 (-11.3776, 14.0705) -> (-11.1857, 14.6267) centre (-11.7265, 14.5021) ccw
  arc A423 (-11.2613, 15.1102) -> (-11.3006, 14.9132) centre (-11.1717, 14.9899) ccw
  arc A424 (-11.1857, 14.6267) -> (-11.3006, 14.9132) centre (-12.1602, 14.4022) ccw
  arc A425 (-11.0551, 15.2617) -> (-11.2613, 15.1102) centre (0, 0) ccw
  arc A426 (-12.2177, 14.1717) -> (-12.4185, 14.1745) centre (-12.3196, 14.0616) ccw
  arc A427 (-13.8321, 12.7987) -> (-14.0046, 12.6098) centre (0, 0) ccw
  arc A428 (-13.6321, 12.8169) -> (-13.3593, 12.6723) centre (-13.0329, 13.6175) ccw
  arc A429 (-13.3593, 12.6723) -> (-12.786, 12.8042) centre (-13.1782, 13.1969) ccw
  arc A430 (-12.786, 12.8042) -> (-12.6533, 13.3773) centre (-13.1782, 13.1969) ccw
  arc A431 (-12.779, 13.8503) -> (-12.7975, 13.6503) centre (-12.6773, 13.74) ccw
  arc A432 (-12.6533, 13.3773) -> (-12.7975, 13.6503) centre (-13.599, 13.0523) ccw
  arc A433 (-12.5898, 14.0225) -> (-12.779, 13.8503) centre (0, 0) ccw
  arc A434 (-13.6321, 12.8169) -> (-13.8321, 12.7987) centre (-13.722, 12.6969) ccw
  arc A435 (-15.0941, 11.2828) -> (-15.2459, 11.0768) centre (0, 0) ccw
  arc A436 (-14.8972, 11.3218) -> (-14.6108, 11.2065) centre (-14.3849, 12.1806) ccw
  arc A437 (-14.6108, 11.2065) -> (-14.0544, 11.3975) centre (-14.4854, 11.7471) ccw
  arc A438 (-14.0544, 11.3975) -> (-13.9823, 11.9814) centre (-14.4854, 11.7471) ccw
  arc A439 (-14.1568, 12.4386) -> (-14.1543, 12.2378) centre (-14.0441, 12.3396) ccw
  arc A440 (-13.9823, 11.9814) -> (-14.1543, 12.2378) centre (-14.8888, 11.5593) ccw
  arc A441 (-13.9866, 12.6297) -> (-14.1568, 12.4386) centre (0, 0) ccw
  arc A442 (-14.8972, 11.3218) -> (-15.0941, 11.2828) centre (-14.974, 11.193) ccw
  arc A443 (-16.1908, 9.6432) -> (-16.3202, 9.4225) centre (0, 0) ccw
  arc A444 (-15.999, 9.7026) -> (-15.7021, 9.6178) centre (-15.5794, 10.6103) ccw
  arc A445 (-15.7021, 9.6178) -> (-15.1687, 9.866) centre (-15.634, 10.1686) ccw
  arc A446 (-15.1687, 9.866) -> (-15.1581, 10.4542) centre (-15.634, 10.1686) ccw
  arc A447 (-15.3794, 10.8907) -> (-15.356, 10.6913) centre (-15.257, 10.804) ccw
  arc A448 (-15.1581, 10.4542) -> (-15.356, 10.6913) centre (-16.0155, 9.9396) ccw
  arc A449 (-15.2302, 11.0985) -> (-15.3794, 10.8907) centre (0, 0) ccw
  arc A450 (-15.999, 9.7026) -> (-16.1908, 9.6432) centre (-16.062, 9.5664) ccw
  arc A451 (-17.1101, 7.898) -> (-17.2158, 7.665) centre (0, 0) ccw
  arc A452 (-16.9256, 7.9771) -> (-16.6214, 7.9238) centre (-16.6031, 8.9237) ccw
  arc A453 (-16.6214, 7.9238) -> (-16.1169, 8.2264) centre (-16.6112, 8.4787) ccw
  arc A454 (-16.1169, 8.2264) -> (-16.1678, 8.8125) centre (-16.6112, 8.4787) ccw
  arc A455 (-16.4336, 9.2234) -> (-16.3894, 9.0276) centre (-16.3028, 9.15) ccw
  arc A456 (-16.1678, 8.8125) -> (-16.3894, 9.0276) centre (-16.9668, 8.2111) ccw
  arc A457 (-16.3068, 9.4457) -> (-16.4336, 9.2234) centre (0, 0) ccw
  arc A458 (-16.9256, 7.9771) -> (-17.1101, 7.898) centre (-16.9739, 7.8351) ccw
  arc A459 (-17.842, 6.0662) -> (-17.9227, 5.8234) centre (0, 0) ccw
  arc A460 (-17.6667, 6.1642) -> (-17.3586, 6.143) centre (-17.4449, 7.1393) ccw
  arc A461 (-17.3586, 6.143) -> (-16.8885, 6.4967) centre (-17.4065, 6.6959) ccw
  arc A462 (-16.8885, 6.4967) -> (-17.0004, 7.0742) centre (-17.4065, 6.6959) ccw
  arc A463 (-17.3077, 7.4551) -> (-17.2432, 7.265) centre (-17.1699, 7.3958) ccw
  arc A464 (-17.0004, 7.0742) -> (-17.2432, 7.265) centre (-17.7321, 6.3926) ccw
  arc A465 (-17.2048, 7.6894) -> (-17.3077, 7.4551) centre (0, 0) ccw
  arc A466 (-17.6667, 6.1642) -> (-17.842, 6.0662) centre (-17.6999, 6.0179) ccw
  arc A467 (-18.3783, 4.168) -> (-18.4332, 3.9181) centre (0, 0) ccw
  arc A468 (-18.2142, 4.2837) -> (-17.9057, 4.2949) centre (-18.0956, 5.2767) ccw
  arc A469 (-17.9057, 4.2949) -> (-17.4751, 4.6958) centre (-18.0111, 4.8398) ccw
  arc A470 (-17.4751, 4.6958) -> (-17.6467, 5.2585) centre (-18.0111, 4.8398) ccw
  arc A471 (-17.9921, 5.6052) -> (-17.9082, 5.4227) centre (-17.8489, 5.5605) ccw
  arc A472 (-17.6467, 5.2585) -> (-17.9082, 5.4227) centre (-18.3032, 4.5041) ccw
  arc A473 (-17.9144, 5.8489) -> (-17.9921, 5.6052) centre (0, 0) ccw
  arc A474 (-18.2142, 4.2837) -> (-18.3783, 4.168) centre (-18.232, 4.1348) ccw
  arc A475 (-18.7133, 2.2241) -> (-18.7418, 1.9698) centre (0, 0) ccw
  arc A476 (-18.5622, 2.3564) -> (-18.2565, 2.3997) centre (-18.548, 3.3563) ccw
  arc A477 (-18.2565, 2.3997) -> (-17.8702, 2.8434) centre (-18.4183, 2.9306) ccw
  arc A478 (-17.8702, 2.8434) -> (-18.0997, 3.3851) centre (-18.4183, 2.9306) ccw
  arc A479 (-18.4795, 3.6938) -> (-18.3769, 3.5211) centre (-18.3324, 3.6644) ccw
  arc A480 (-18.0997, 3.3851) -> (-18.3769, 3.5211) centre (-18.6737, 2.5662) ccw
  arc A481 (-18.4276, 3.9443) -> (-18.4795, 3.6938) centre (0, 0) ccw
  arc A482 (-18.5622, 2.3564) -> (-18.7133, 2.2241) centre (-18.5643, 2.2064) ccw
  point P0 (-18.7389, 1.9965)
  point P1 (-18.4332, 3.9181)
  point P2 (-17.9227, 5.8234)
  point P3 (-17.2158, 7.665)
  point P4 (-16.3202, 9.4225)
  point P5 (-15.2459, 11.0768)
  point P6 (-14.0046, 12.6098)
  point P7 (-12.6098, 14.0046)
  point P8 (-11.0768, 15.2459)
  point P9 (-9.4225, 16.3202)
  point P10 (-7.665, 17.2158)
  point P11 (-5.8234, 17.9227)
  point P12 (-3.9181, 18.4332)
  point P13 (-1.9698, 18.7418)
  point P14 (0, 18.845)
  point P15 (1.9698, 18.7418)
  point P16 (3.9181, 18.4332)
  point P17 (5.8234, 17.9227)
  point P18 (7.665, 17.2158)
  point P19 (9.4225, 16.3202)
  point P20 (11.0768, 15.2459)
  point P21 (12.6098, 14.0046)
  point P22 (14.0046, 12.6098)
  point P23 (15.2459, 11.0768)
  point P24 (16.3202, 9.4225)
  point P25 (17.2158, 7.665)
  point P26 (17.9227, 5.8234)
  point P27 (18.4332, 3.9181)
  point P28 (18.7418, 1.9698)
  point P29 (18.845, 0)
  point P30 (18.7418, -1.9698)
  point P31 (18.4332, -3.9181)
  point P32 (17.9227, -5.8234)
  point P33 (17.2158, -7.665)
  point P34 (16.3202, -9.4225)
  point P35 (15.2459, -11.0768)
  point P36 (14.0046, -12.6098)
  point P37 (12.6098, -14.0046)
  point P38 (11.0768, -15.2459)
  point P39 (9.4225, -16.3202)
  point P40 (7.665, -17.2158)
  point P41 (5.8234, -17.9227)
  point P42 (3.9181, -18.4332)
  point P43 (1.9698, -18.7418)
  point P44 (0, -18.845)
  point P45 (-1.9698, -18.7418)
  point P46 (-3.9181, -18.4332)
  point P47 (-5.8234, -17.9227)
  point P48 (-7.665, -17.2158)
  point P49 (-9.4225, -16.3202)
  point P50 (-11.0768, -15.2459)
  point P51 (-12.6098, -14.0046)
  point P52 (-14.0046, -12.6098)
  point P53 (-15.2459, -11.0768)
  point P54 (-16.3202, -9.4225)
  point P55 (-17.2158, -7.665)
  point P56 (-17.9227, -5.8234)
  point P57 (-18.4332, -3.9181)
  point P58 (-18.7418, -1.9698)
  point P59 (-18.845, 0)
  dimension "d4" = 0.254
  dimension "d5" = 0.15
  dimension "d6" = 0.4
  dimension "d7" = 1
  dimension "d8" = 0.555
  dimension "d9" = 0.75
  dimension "d10" = 1
  dimension "d33" = 360
  constraints: 964 point on circle, 482 centre point, 6 symmetric about line, 4 end point, 3 coincident, 3 point on line, 3 tangent, 1 horizontal, 1 horizontal alignment, 1386 other
  measures "d4" distance of L0.end A1.end
  measures "d5" radius of A2
  measures "d6" distance from line of L1 A3.centre
  measures "d7" radius of A3
  measures "d8" radius of A4
  measures "d9" distance of A4.end A5.start
  measures "d10" distance of A5.start A1.end
extrude "Extrusion6" cut sketch "Sketch2" against normal through all
sketch "Sketch6" plane through (0, 8, 0) normal (0, 1, 0) x (1, 0, 0)
  circle A0 centre (0, 0) radius 22
  dimension "d37" = 44
  constraints: 1 centre point, 1 coincident
  measures "d37" diameter of A0
extrude "Extrusion7" add sketch "Sketch6" along normal blind 1.5
sketch "Sketch7" plane through (0, 0, 0) normal (0, -1, 0) x (1, 0, 0)
  circle A0 centre (0, 0) radius 22 projected
extrude "Extrusion8" add sketch "Sketch7" along normal blind 1.5
sketch "Sketch8" plane through (0, 9.5, 0) normal (0, 1, 0) x (1, 0, 0)
  circle A0 centre (0, 0) radius 12
  dimension "d42" = 24
  constraints: 1 centre point, 1 coincident
  measures "d42" diameter of A0
extrude "Extrusion9" add sketch "Sketch8" along normal blind 6
sketch "Sketch9" plane through (0, 15.5, 0) normal (0, 1, 0) x (1, 0, 0)
  circle A0 centre (0, 0) radius 6
  dimension "d45" = 12
  constraints: 1 centre point, 1 coincident
  measures "d45" diameter of A0
extrude "Extrusion10" cut sketch "Sketch9" against normal through all
chamfer "Chamfer3" distance 0.5 angle 45 2 edges at (-22, 8, 0) (-22, 0, 0)
chamfer "Chamfer4" distance 1.5 angle 45 1 edges at (-12, 9.5, 0)
chamfer "Chamfer5" distance 0.5 angle 45 1 edges at (-12, 15.5, 0)
body "Solid1"
